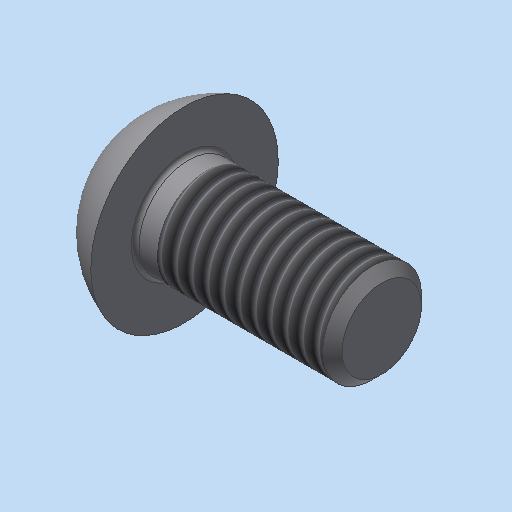
# Autodesk Inventor part: Hexagon_socket_button_head_screw_ISO7380_M5x10
Saved by Autodesk Inventor 2023.3 (Build 273359000, 359)
## iProperties
Shininess: 64.0
Length Units: 11269
Angle Units: 11279
Time Units: 11290
Mass Units: 11283
Length Display Precision: 3
Angle Display Precision: 2
Compacted: True
Part Number: Hexagon_socket_button_head_screw_ISO7380_M5x10
Document SubType Name: Modeling
Created: 2004-04-02
Material: xStahl_AnP_Dummymaterial
Description: =<RBPARTNOTITLE2>
Vendor: NORM8
Designer: S.Riedelsheimer
Manufacturer: Standard
Standards Organization: Custom
Mass: 2.48142 g
Surface Area: 3.44251 cm^2
Volume: 0.316104 cm^3
Density: 7.85 g/cm^3
Appearance: RGB(178,178,178)
Density: 0.0
Volumn: 0.0
Area: 0.0
PropertySet Name: Model Information
Control State: 0
Master: False
Checked Out: False
CNS_NB: Hexagon socket button head screw ISO7380-M5x10
CNS_NN: ISO 7380
CNS_NT: Hexagon socket button head screw
CNS_NBSYN: Hexagon socket button head screw ISO7380-M$D.x$L.
CNS_LINA: Hexagon socket button head screw ISO7380-M5x10
CNS_D: 5.000
CNS_D3: 4.019
CNS_P: 0.800
CNS_L: 10.000
CNS_S: 3.000
CNS_A: 1.600
CNS_DA: 5.700
CNS_DK: 9.500
CNS_K: 2.750
CNS_R: 0.200
CNS_T: 1.560
CNS_KT: DUMMY
PSOL_IDENT_0: {C:\partsolutions8\data\23d-libs\bosch_bamberg\schrauben\spezialschrauben\iso_7380.prj},182 {M=Nenng
PSOL_IDENT_1: ewinde},{VTYP=3D},{NB=Hexagon socket button head screw ISO7380-M5x10},{NN=ISO 7380},{DATE=26.11.2003
PSOL_IDENT_2: },{GEOMDATE=26.11.2003},{VERSION=v1},{LINEID=90},{LINESUBID=-1},{WBVAR=}  {NB=Hexagon socket button
PSOL_IDENT_3: head screw ISO7380-M5x10},{LINA=Hexagon socket button head screw ISO7380-M5x10},{KT=DUMMY},{IDNR=},{
PSOL_IDENT_4: D=5.000},{D3=4.019},{P=0.800},{L=10.000},{S=3.000},{A=1.600},{DA=5.700},{DK=9.500},{K=2.750},{R=0.20
PSOL_IDENT_5: 0},{T=1.560}
RBPARTNOTITLE2: Schraube mit abgeflachtem halbrundkopf und Innensechskant
RBPARTNOTITLE1: Hexagon socket button head screw
RBPARTMADEOF: ISO 7380-1 - M5x10 - St
RBDRAWINGMISSINGSPEC: --
AnP_Kategorie: 2
Title: Hexagon socket button head screw ISO7380-M5x10
Author: S.Riedelsheimer
Keywords: =<RBPARTMADEOF>
Comments: =<RBSURFACE2>
Revision Number: 01
Autodesk Inventor part; units mm, degrees
sketch "Sketch_1" plane through (0, 0, 0) normal (0, 1, 0) x (-1, 0, 0)
  line L0 (0.3817, 0) -> (-10, 0)
  line L1 (-10, 0) -> (-10, 2.0095)
  line L2 (-10, 2.0095) -> (-9.5095, 2.5)
  line L3 (-9.5095, 2.5) -> (-0.2, 2.5)
  arc A0 (-0.2, 2.5) -> (0, 2.7) centre (-0.2, 2.7) ccw
  line L4 (0, 2.7) -> (0, 4.75)
  arc A1 (2.75, 2.5) -> (0, 4.75) centre (-1.5909, 0) ccw
  line L5 (2.75, 2.5) -> (2.75, 1.7321)
  line L6 (2.75, 1.7321) -> (2.4179, 1.4)
  line L7 (2.4179, 1.4) -> (1.19, 1.4)
  line L8 (1.19, 1.4) -> (0.3817, 0)
  line L9 (0.3817, 0) -> (-10, 0)
  constraints: 20 end point, 4 point on circle, 2 centre point
revolve "Drehung1" add sketch "Sketch_1" angle 360 about axis through (-0.3817, 0, 0) along (1, 0, 0)
thread "Gewinde1" size "M5x0.8" class "6g" standard "ANSI Metric M Profile" length 8.4
sketch "Sketch_2" plane through (-2.75, 0, 0) normal (1, 0, 0) x (0, 0, -1)
  line L0 (-1.5, 0.866) -> (-1.5, -0.866)
  line L1 (-1.5, -0.866) -> (0, -1.7321)
  line L2 (0, -1.7321) -> (1.5, -0.866)
  line L3 (1.5, -0.866) -> (1.5, 0.866)
  line L4 (1.5, 0.866) -> (0, 1.7321)
  line L5 (0, 1.7321) -> (-1.5, 0.866)
  constraints: 12 end point
extrude "Extrusion1" cut sketch "Sketch_2" along normal blind 1.56
ref_plane "IP1_XY" through (0, 0, 0) normal (1, 0, 0) x (0, 0, -1)
ref_plane "IP1_YZ" through (0, 0, 0) normal (0, 0, -1) x (0, 1, 0)
ref_plane "IP2_XY" through (10, 0, 0) normal (1, 0, 0) x (0, 0, -1)
ref_plane "IP2_YZ" through (10, 0, 0) normal (0, 0, -1) x (0, 1, 0)
